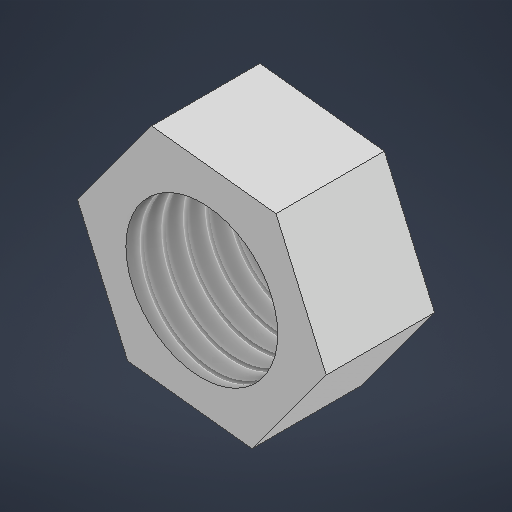
# Autodesk Inventor part: washer
Saved by Autodesk Inventor 2025.2 (Build 292293000, 293)
## iProperties
Created: 2024-12-25
Part Number: washer
Material: Generic
Document SubType Name: Modeling
Designer: user
Density: 1 g/cm^3
Appearance: Default
Author: user
Autodesk Inventor part; units mm, degrees
ref_plane "YZ Plane" through (0, 0, 0) normal (1, 0, 0) x (0, 1, 0)
ref_plane "XZ Plane" through (0, 0, 0) normal (0, 1, 0) x (-1, 0, 0)
ref_plane "XY Plane" through (0, 0, 0) normal (0, 0, 1) x (1, 0, 0)
sketch "Sketch1" plane through (0, 0, 0) normal (0, 0, 1) x (1, 0, 0)
  point P0 (0, 0)
sketch "Sketch2" plane through (0, 0, 0) normal (0, 0, 1) x (1, 0, 0)
  line L0 (4.634, -10.3296) -> (-6.8424, -9.0545)
  line L1 (-6.8424, -9.0545) -> (-11.4764, 1.5219)
  line L2 (-11.4764, 1.5219) -> (-4.634, 10.8232)
  line L3 (-4.634, 10.8232) -> (6.8424, 9.5481)
  line L4 (6.8424, 9.5481) -> (11.4764, -1.0282)
  line L5 (11.4764, -1.0282) -> (4.634, -10.3296)
  circle A0 centre (0, 0) radius 7
  point P0 (0, 0.2468)
  dimension "d0" = 20
  dimension "d1" = 14
  constraints: 12 end point, 1 centre point, 1 coincident, 13 other
  measures "d0" distance between parallel lines of L3 L0
  measures "d1" diameter of A0
extrude "Extrusion1" add sketch "Sketch2" along normal blind 10
thread "Thread1" size "M14x2" class "6H" standard "ANSI Metric M Profile" length 50
body "Solid1"
